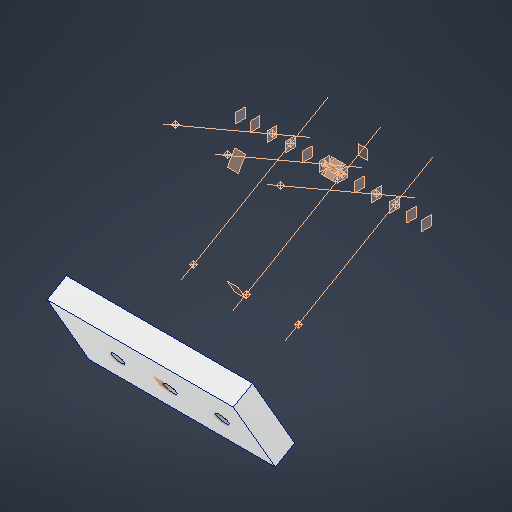
# Autodesk Inventor part: Cam_Cover_B
Saved by Autodesk Inventor 2027.1 (Build 311270010, 270A)
## iProperties
Created: 2026-10-17
Part Number: Cam_Cover_B
Material: Aluminum 6061
Document SubType Name: Modeling
Designer: kashyap
Density: 2.7 g/cm^3
Appearance: Aluminum - Flat
Material_Status: Assumed for this reconstruction
Author: kashyap
Autodesk Inventor part; units mm, degrees
ref_plane "YZ Plane" through (0, 0, 0) normal (1, 0, 0) x (0, 1, 0)
ref_plane "XZ Plane" through (0, 0, 0) normal (0, 1, 0) x (-1, 0, 0)
ref_plane "XY Plane" through (0, 0, 0) normal (0, 0, 1) x (1, 0, 0)
derived "V6_Engine_Master.ipt"
ref_plane "Bank_A_Plane" through (0, 0, 0) normal (0, 0.8660254, -0.5) x (-1, 0, 0)
ref_plane "Bank_B_Plane" through (0, 0, 0) normal (0, 0.8660254, 0.5) x (-1, 0, 0)
ref_plane "Bank_A_Perp_Plane" through (0, 0, 0) normal (0, 0.5, 0.8660254) x (-1, 0, 0)
ref_plane "Bank_B_Perp_Plane" through (0, 0, 0) normal (0, -0.5, 0.8660254) x (-1, 0, 0)
ref_plane "Bank_A_Deck_Plane" through (0, 112.9, 195.5485) normal (0, 0.5, 0.8660254) x (-1, 0, 0)
ref_plane "Bank_B_Deck_Plane" through (0, -112.9, 195.5485) normal (0, -0.5, 0.8660254) x (-1, 0, 0)
ref_plane "Cyl_A1_Station_Plane" through (-123.8, 0, 0) normal (1, 0, 0) x (0, 1, 0)
ref_plane "Cyl_A2_Station_Plane" through (-18.3, 0, 0) normal (1, 0, 0) x (0, 1, 0)
ref_plane "Cyl_A3_Station_Plane" through (87.2, 0, 0) normal (1, 0, 0) x (0, 1, 0)
ref_plane "Cyl_B1_Station_Plane" through (-87.2, 0, 0) normal (1, 0, 0) x (0, 1, 0)
ref_plane "Cyl_B2_Station_Plane" through (18.3, 0, 0) normal (1, 0, 0) x (0, 1, 0)
ref_plane "Cyl_B3_Station_Plane" through (123.8, 0, 0) normal (1, 0, 0) x (0, 1, 0)
ref_plane "Main_Bearing_Station_1" through (-158.25, 0, 0) normal (1, 0, 0) x (0, 1, 0)
ref_plane "Main_Bearing_Station_2" through (-52.75, 0, 0) normal (1, 0, 0) x (0, 1, 0)
ref_plane "Main_Bearing_Station_3" through (52.75, 0, 0) normal (1, 0, 0) x (0, 1, 0)
ref_plane "Main_Bearing_Station_4" through (158.25, 0, 0) normal (1, 0, 0) x (0, 1, 0)
ref_plane "Front_Interface" through (-188.25, 0, 0) normal (1, 0, 0) x (0, 1, 0)
ref_plane "Rear_Interface" through (188.25, 0, 0) normal (1, 0, 0) x (0, 1, 0)
ref_plane "Oil_Pan_Plane" through (0, 0, -60) normal (0, 0, 1) x (1, 0, 0)
ref_plane "Cover_Joint_Plane" through (0, -178.25, 308.7381) normal (0, -0.5, 0.8660254) x (-1, 0, 0)
ref_plane "Cover_Top_Plane" through (0, -200.75, 347.7092) normal (0, -0.5, 0.8660254) x (-1, 0, 0)
sketch "SK_Cover_Shell" plane through (18.3, -178.25, 308.7381) normal (0, -0.5, 0.8660254) x (1, 0, 0)
  line L0 (-206.55, 119) -> (-206.55, -119) construction
  line L1 (169.95, 119) -> (169.95, -119) construction
  line L2 (-281.85, 0) -> (245.25, 0) construction
  line L3 (-206.55, 85) -> (169.95, 85)
  line L4 (169.95, 85) -> (169.95, -85)
  line L5 (169.95, -85) -> (-206.55, -85)
  line L6 (-206.55, -85) -> (-206.55, 85)
  dimension "d21" = 85
  dimension "d22" = 85
  constraints: 8 end point, 2 collinear, 2 parallel, 1 horizontal, 1 perpendicular
  measures "d21" distance between parallel lines of L3 L2
  measures "d22" distance between parallel lines of L5 L2
extrude "Cover_Shell" add sketch "SK_Cover_Shell" along normal blind 45
sketch "SK_Cover_Cavity" plane through (18.3, -178.25, 308.7381) normal (0, -0.5, 0.8660254) x (1, 0, 0)
  line L0 (-206.55, 146.2798) -> (-206.55, -146.2798) construction
  line L1 (169.95, 146.2798) -> (169.95, -146.2798) construction
  line L2 (-281.85, 0) -> (245.25, 0) construction
  line L3 (-201.55, 80) -> (164.95, 80)
  line L4 (164.95, 80) -> (164.95, -80)
  line L5 (164.95, -80) -> (-201.55, -80)
  line L6 (-201.55, -80) -> (-201.55, 80)
  dimension "d25" = 5
  dimension "d26" = 5
  dimension "d27" = 80
  dimension "d28" = 80
  constraints: 8 end point, 2 parallel, 1 horizontal, 1 perpendicular
  measures "d25" distance between parallel lines of L6 L0
  measures "d26" distance between parallel lines of L4 L1
  measures "d27" distance between parallel lines of L3 L2
  measures "d28" distance between parallel lines of L5 L2
extrude "Cover_Cavity" cut sketch "SK_Cover_Cavity" along normal blind 40
sketch "SK_Plug_Tube_Holes" plane through (18.3, -200.75, 347.7092) normal (0, -0.5, 0.8660254) x (1, 0, 0)
  circle A0 centre (-105.5, 0) radius 12.5
  circle A1 centre (0, 0) radius 12.5
  circle A2 centre (105.5, 0) radius 12.5
  dimension "d31" = 25
  dimension "d32" = 25
  dimension "d33" = 25
  constraints: 3 centre point
  measures "d31" diameter of A0
  measures "d32" diameter of A1
  measures "d33" diameter of A2
extrude "Plug_Tube_Holes" cut sketch "SK_Plug_Tube_Holes" against normal blind 6
sketch "SK_Cam_Nose_Holes" plane through (-188.25, 0, 0) normal (1, 0, 0) x (0, 1, 0)
  circle A0 centre (-136.0657, 334.29) radius 12.5
  circle A1 centre (-224.6316, 288.2542) radius 12.5
  dimension "d38" = 25
  dimension "d39" = 25
  constraints: 2 centre point
  measures "d38" diameter of A0
  measures "d39" diameter of A1
extrude "Cam_Nose_Holes" cut sketch "SK_Cam_Nose_Holes" along normal blind 6
equation "\"d21\" = Head_Half_Width"
equation "\"d22\" = Head_Half_Width"
equation "\"d23\" = Cam_Cover_Height"
equation "\"d25\" = Cam_Cover_Wall"
equation "\"d26\" = Cam_Cover_Wall"
equation "\"d27\" = Head_Half_Width - Cam_Cover_Wall"
equation "\"d28\" = Head_Half_Width - Cam_Cover_Wall"
equation "\"d29\" = Cam_Cover_Height - Cam_Cover_Wall"
equation "\"Head_Half_Width\" = 85"
equation "\"Cam_Cover_Height\" = 45"
equation "\"Cam_Cover_Wall\" = 5"
body "Solid1"
